Autodesk Fusion 360 part; units mm, degrees
(part 2 of 8)
extrude "Diffuser open rear skirt" add sketch "Diffuser hollow skirt outside profile" against normal blind 2.6 bodies 4
ref_plane "WorkPlane13" through (12.125, -2.4482, 27.9828) normal (0, -0.087156, 0.996195) x (1, 0, 0)
sketch "Diffuser optical cavity profile" plane through (0, -2.4482, 27.9828) normal (0, -0.087156, 0.996195) x (1, 0, 0)
  line L0 (7.7, 94.1972) -> (72.3, 94.1972)
  line L1 (72.3, 94.1972) -> (72.3, 101.7972)
  line L2 (72.3, 101.7972) -> (7.7, 101.7972)
  line L3 (7.7, 101.7972) -> (7.7, 94.1972)
  dimension "d533" = 7.7
  dimension "d534" = 94.1972
  dimension "d535" = 64.6
  dimension "d536" = 7.6
  constraint horizontal L0
  constraint vertical L1
  constraint horizontal L2
  constraint vertical L3
  measures "d533" horizontal distance of origin L0.start
  measures "d534" vertical distance of origin L0.start
  measures "d535" distance of L0.start L0.end
  measures "d536" distance of L0.end L1.end
extrude "Hollow diffuser from inside" cut sketch "Diffuser optical cavity profile" against normal blind 7 bodies 4
sketch "Diffuser right wire exit profile" plane through (0, -2.2216, 25.3927) normal (0, -0.087156, 0.996195) x (1, 0, 0)
  line L0 (71.5, 95.9972) -> (76.5, 95.9972)
  line L1 (76.5, 95.9972) -> (76.5, 99.9972)
  line L2 (76.5, 99.9972) -> (71.5, 99.9972)
  line L3 (71.5, 99.9972) -> (71.5, 95.9972)
  dimension "d539" = 71.5
  dimension "d540" = 95.9972
  dimension "d541" = 5
  dimension "d542" = 4
  constraint horizontal L0
  constraint vertical L1
  constraint horizontal L2
  constraint vertical L3
  measures "d539" horizontal distance of origin L0.start
  measures "d540" vertical distance of origin L0.start
  measures "d541" distance of L0.start L0.end
  measures "d542" distance of L0.end L1.end
extrude "Diffuser right wire exit" cut sketch "Diffuser right wire exit profile" against normal blind 6 bodies 4
sketch "Deep diffuser skirt clearance profile" plane through (0, -2.2739, 25.9904) normal (0, -0.087156, 0.996195) x (1, 0, 0)
  line L0 (5, 91.4972) -> (75, 91.4972)
  line L1 (75, 91.4972) -> (75, 104.4972)
  line L2 (75, 104.4972) -> (5, 104.4972)
  line L3 (5, 104.4972) -> (5, 91.4972)
  dimension "d545" = 5
  dimension "d546" = 91.4972
  dimension "d547" = 70
  dimension "d548" = 13
  constraint horizontal L0
  constraint vertical L1
  constraint horizontal L2
  constraint vertical L3
  measures "d545" horizontal distance of origin L0.start
  measures "d546" vertical distance of origin L0.start
  measures "d547" distance of L0.start L0.end
  measures "d548" distance of L0.end L1.end
extrude "Clear carrier around hollow diffuser" cut sketch "Deep diffuser skirt clearance profile" against normal blind 3.4 bodies 2
sketch "LED rear support web profile" plane through (0, -2.2739, 25.9904) normal (0, -0.087156, 0.996195) x (1, 0, 0)
  line L0 (6.3, 108.1799) -> (73.7, 108.1799)
  line L1 (73.7, 108.1799) -> (73.7, 112.1799)
  line L2 (73.7, 112.1799) -> (6.3, 112.1799)
  line L3 (6.3, 112.1799) -> (6.3, 108.1799)
  dimension "d551" = 6.3
  dimension "d552" = 108.1799
  dimension "d553" = 67.4
  dimension "d554" = 4
  constraint horizontal L0
  constraint vertical L1
  constraint horizontal L2
  constraint vertical L3
  measures "d551" horizontal distance of origin L0.start
  measures "d552" vertical distance of origin L0.start
  measures "d553" distance of L0.start L0.end
  measures "d554" distance of L0.end L1.end
extrude "LED rear support web" add sketch "LED rear support web profile" against normal blind 5.8 bodies 2
ref_plane "WorkPlane14" through (12.125, -1.9775, 22.6033) normal (0, -0.087156, 0.996195) x (1, 0, 0)
sketch "Continuous LED tray profile" plane through (0, -1.9775, 22.6033) normal (0, -0.087156, 0.996195) x (1, 0, 0)
  line L0 (6.3, 92.7972) -> (73.7, 92.7972)
  line L1 (73.7, 92.7972) -> (73.7, 114.4037)
  line L2 (73.7, 114.4037) -> (6.3, 114.4037)
  line L3 (6.3, 114.4037) -> (6.3, 92.7972)
  dimension "d559" = 6.3
  dimension "d560" = 92.7972
  dimension "d561" = 67.4
  dimension "d562" = 21.6065
  constraint horizontal L0
  constraint vertical L1
  constraint horizontal L2
  constraint vertical L3
  measures "d559" horizontal distance of origin L0.start
  measures "d560" vertical distance of origin L0.start
  measures "d561" distance of L0.start L0.end
  measures "d562" distance of L0.end L1.end
extrude "Continuous LED mounting crossbar" add sketch "Continuous LED tray profile" against normal blind 2.4 bodies 2
sketch "LED tray right wire relief profile" plane through (0, -1.9775, 22.6033) normal (0, -0.087156, 0.996195) x (1, 0, 0)
  line L0 (71.5, 95.9972) -> (75.5, 95.9972)
  line L1 (75.5, 95.9972) -> (75.5, 99.9972)
  line L2 (75.5, 99.9972) -> (71.5, 99.9972)
  line L3 (71.5, 99.9972) -> (71.5, 95.9972)
  dimension "d565" = 71.5
  dimension "d566" = 95.9972
  dimension "d567" = 4
  dimension "d568" = 4
  constraint horizontal L0
  constraint vertical L1
  constraint horizontal L2
  constraint vertical L3
  measures "d565" horizontal distance of origin L0.start
  measures "d566" vertical distance of origin L0.start
  measures "d567" distance of L0.start L0.end
  measures "d568" distance of L0.end L1.end
extrude "LED tray right wire relief" cut sketch "LED tray right wire relief profile" against normal blind 3.4 bodies 2
sketch "OLED seat 1 profile" plane through (0, -2.5179, 28.7797) normal (0, -0.087156, 0.996195) x (1, 0, 0)
  line L0 (5.75, 59.4972) -> (41.75, 59.4972)
  line L1 (41.75, 59.4972) -> (41.75, 62.4972)
  line L2 (41.75, 62.4972) -> (5.75, 62.4972)
  line L3 (5.75, 62.4972) -> (5.75, 59.4972)
  dimension "d571" = 5.75
  dimension "d572" = 59.4972
  dimension "d573" = 36
  dimension "d574" = 3
  constraint horizontal L0
  constraint vertical L1
  constraint horizontal L2
  constraint vertical L3
  measures "d571" horizontal distance of origin L0.start
  measures "d572" vertical distance of origin L0.start
  measures "d573" distance of L0.start L0.end
  measures "d574" distance of L0.end L1.end
extrude "OLED opposed locating ledge 1" add sketch "OLED seat 1 profile" against normal blind 2.8 bodies 1
sketch "OLED seat 2 profile" plane through (0, -2.5179, 28.7797) normal (0, -0.087156, 0.996195) x (1, 0, 0)
  line L0 (5.75, 88.4972) -> (41.75, 88.4972)
  line L1 (41.75, 88.4972) -> (41.75, 91.4972)
  line L2 (41.75, 91.4972) -> (5.75, 91.4972)
  line L3 (5.75, 91.4972) -> (5.75, 88.4972)
  dimension "d577" = 5.75
  dimension "d578" = 88.4972
  dimension "d579" = 36
  dimension "d580" = 3
  constraint horizontal L0
  constraint vertical L1
  constraint horizontal L2
  constraint vertical L3
  measures "d577" horizontal distance of origin L0.start
  measures "d578" vertical distance of origin L0.start
  measures "d579" distance of L0.start L0.end
  measures "d580" distance of L0.end L1.end
extrude "OLED opposed locating ledge 2" add sketch "OLED seat 2 profile" against normal blind 2.8 bodies 1
sketch "OLED PCB carrier clearance profile" plane through (0, -2.2739, 25.9904) normal (0, -0.087156, 0.996195) x (1, 0, 0)
  line L0 (5.55, 59.2972) -> (41.95, 59.2972)
  line L1 (41.95, 59.2972) -> (41.95, 93.6972)
  line L2 (41.95, 93.6972) -> (5.55, 93.6972)
  line L3 (5.55, 93.6972) -> (5.55, 59.2972)
  dimension "d583" = 5.55
  dimension "d584" = 59.2972
  dimension "d585" = 36.4
  dimension "d586" = 34.4
  constraint horizontal L0
  constraint vertical L1
  constraint horizontal L2
  constraint vertical L3
  measures "d583" horizontal distance of origin L0.start
  measures "d584" vertical distance of origin L0.start
  measures "d585" distance of L0.start L0.end
  measures "d586" distance of L0.end L1.end
extrude "OLED PCB clearance in carrier" cut sketch "OLED PCB carrier clearance profile" against normal blind 1.8 bodies 2
ref_plane "WorkPlane15" through (12.125, -2.117, 24.1972) normal (0, -0.087156, 0.996195) x (1, 0, 0)
sketch "OLED front clamp root profile" plane through (0, -2.2739, 25.9904) normal (0, -0.087156, 0.996195) x (1, 0, 0)
  line L0 (18, 58.4972) -> (32, 58.4972)
  line L1 (32, 58.4972) -> (32, 59.4972)
  line L2 (32, 59.4972) -> (18, 59.4972)
  line L3 (18, 59.4972) -> (18, 58.4972)
  dimension "d591" = 18
  dimension "d592" = 58.4972
  dimension "d593" = 14
  dimension "d594" = 1
  constraint horizontal L0
  constraint vertical L1
  constraint horizontal L2
  constraint vertical L3
  measures "d591" horizontal distance of origin L0.start
  measures "d592" vertical distance of origin L0.start
  measures "d593" distance of L0.start L0.end
  measures "d594" distance of L0.end L1.end
extrude "OLED front clamp root" add sketch "OLED front clamp root profile" against normal blind 3.8 bodies 2
sketch "OLED front opposed clamp profile" plane through (0, -2.117, 24.1972) normal (0, -0.087156, 0.996195) x (1, 0, 0)
  line L0 (18, 58.4972) -> (32, 58.4972)
  line L1 (32, 58.4972) -> (32, 62.4972)
  line L2 (32, 62.4972) -> (18, 62.4972)
  line L3 (18, 62.4972) -> (18, 58.4972)
  dimension "d597" = 18
  dimension "d598" = 58.4972
  dimension "d599" = 14
  dimension "d600" = 4
  constraint horizontal L0
  constraint vertical L1
  constraint horizontal L2
  constraint vertical L3
  measures "d597" horizontal distance of origin L0.start
  measures "d598" vertical distance of origin L0.start
  measures "d599" distance of L0.start L0.end
  measures "d600" distance of L0.end L1.end
extrude "OLED front opposed clamp" add sketch "OLED front opposed clamp profile" against normal blind 2 bodies 2
sketch "OLED rear clamp connecting bridge profile" plane through (0, -1.9775, 22.6033) normal (0, -0.087156, 0.996195) x (1, 0, 0)
  line L0 (18, 89.2972) -> (32, 89.2972)
  line L1 (32, 89.2972) -> (32, 93.0972)
  line L2 (32, 93.0972) -> (18, 93.0972)
  line L3 (18, 93.0972) -> (18, 89.2972)
  dimension "d603" = 18
  dimension "d604" = 89.2972
  dimension "d605" = 14
  dimension "d606" = 3.8
  constraint horizontal L0
  constraint vertical L1
  constraint horizontal L2
  constraint vertical L3
  measures "d603" horizontal distance of origin L0.start
  measures "d604" vertical distance of origin L0.start
  measures "d605" distance of L0.start L0.end
  measures "d606" distance of L0.end L1.end
extrude "OLED rear clamp connecting bridge" add sketch "OLED rear clamp connecting bridge profile" against normal blind 2.4 bodies 2
sketch "OLED rear opposed clamp profile" plane through (0, -2.117, 24.1972) normal (0, -0.087156, 0.996195) x (1, 0, 0)
  line L0 (18, 89.4972) -> (32, 89.4972)
  line L1 (32, 89.4972) -> (32, 91.4972)
  line L2 (32, 91.4972) -> (18, 91.4972)
  line L3 (18, 91.4972) -> (18, 89.4972)
  dimension "d609" = 18
  dimension "d610" = 89.4972
  dimension "d611" = 14
  dimension "d612" = 2
  constraint horizontal L0
  constraint vertical L1
  constraint horizontal L2
  constraint vertical L3
  measures "d609" horizontal distance of origin L0.start
  measures "d610" vertical distance of origin L0.start
  measures "d611" distance of L0.start L0.end
  measures "d612" distance of L0.end L1.end
extrude "OLED rear opposed clamp" add sketch "OLED rear opposed clamp profile" against normal blind 2 bodies 2
sketch "OLED PCB carrier clearance profile (1)" plane through (0, -2.2739, 25.9904) normal (0, -0.087156, 0.996195) x (1, 0, 0)
  line L0 (5.55, 59.2972) -> (41.95, 59.2972)
  line L1 (41.95, 59.2972) -> (41.95, 93.6972)
  line L2 (41.95, 93.6972) -> (5.55, 93.6972)
  line L3 (5.55, 93.6972) -> (5.55, 59.2972)
  dimension "d615" = 5.55
  dimension "d616" = 59.2972
  dimension "d617" = 36.4
  dimension "d618" = 34.4
  constraint horizontal L0
  constraint vertical L1
  constraint horizontal L2
  constraint vertical L3
  measures "d615" horizontal distance of origin L0.start
  measures "d616" vertical distance of origin L0.start
  measures "d617" distance of L0.start L0.end
  measures "d618" distance of L0.end L1.end
extrude "OLED PCB clearance in carrier (1)" cut sketch "OLED PCB carrier clearance profile (1)" against normal blind 1.8 bodies 2
ref_plane "WorkPlane16" through (0, 0, 26.3) normal (0, 0, 1) x (1, 0, 0)
sketch "PCB1 perimeter support profile" plane through (0, 0, 26.3) normal (0, 0, 1) x (1, 0, 0)
  line L0 (3.2, 62.2) -> (4.8, 62.2)
  line L1 (4.8, 62.2) -> (4.8, 66.2)
  line L2 (4.8, 66.2) -> (3.2, 66.2)
  line L3 (3.2, 66.2) -> (3.2, 62.2)
  dimension "d623" = 3.2
  dimension "d624" = 62.2
  dimension "d625" = 1.6
  dimension "d626" = 4
  constraint horizontal L0
  constraint vertical L1
  constraint horizontal L2
  constraint vertical L3
  measures "d623" horizontal distance of origin L0.start
  measures "d624" vertical distance of origin L0.start
  measures "d625" distance of L0.start L0.end
  measures "d626" distance of L0.end L1.end
sketch "PCB1 short post bridge profile" plane through (0, 0, 26.3) normal (0, 0, 1) x (1, 0, 0)
  line L0 (3.2, 62.2) -> (7, 62.2)
  line L1 (7, 62.2) -> (7, 66.2)
  line L2 (7, 66.2) -> (3.2, 66.2)
  line L3 (3.2, 66.2) -> (3.2, 62.2)
  dimension "d629" = 3.2
  dimension "d630" = 62.2
  dimension "d631" = 3.8
  dimension "d632" = 4
  constraint horizontal L0
  constraint vertical L1
  constraint horizontal L2
  constraint vertical L3
  measures "d629" horizontal distance of origin L0.start
  measures "d630" vertical distance of origin L0.start
  measures "d631" distance of L0.start L0.end
  measures "d632" distance of L0.end L1.end
sketch "PCB1 post profile" plane through (0, 0, 22.3) normal (0, 0, 1) x (1, 0, 0)
  circle A0 centre (7, 64.2) radius 2.2
  dimension "d635" = 7
  dimension "d636" = 64.2
  dimension "d637" = 4.4
  measures "d635" horizontal distance of origin A0.centre
  measures "d636" vertical distance of origin A0.centre
  measures "d637" diameter of A0
sketch "PCB1 M2 pilot profile" plane through (0, 0, 22.3) normal (0, 0, 1) x (1, 0, 0)
  circle A0 centre (7, 64.2) radius 0.85
  dimension "d640" = 7
  dimension "d641" = 64.2
  dimension "d642" = 1.7
  measures "d640" horizontal distance of origin A0.centre
  measures "d641" vertical distance of origin A0.centre
  measures "d642" diameter of A0
sketch "PCB2 perimeter support profile" plane through (0, 0, 26.3) normal (0, 0, 1) x (1, 0, 0)
  line L0 (75.2, 62.2) -> (76.8, 62.2)
  line L1 (76.8, 62.2) -> (76.8, 66.2)
  line L2 (76.8, 66.2) -> (75.2, 66.2)
  line L3 (75.2, 66.2) -> (75.2, 62.2)
  dimension "d645" = 75.2
  dimension "d646" = 62.2
  dimension "d647" = 1.6
  dimension "d648" = 4
  constraint horizontal L0
  constraint vertical L1
  constraint horizontal L2
  constraint vertical L3
  measures "d645" horizontal distance of origin L0.start
  measures "d646" vertical distance of origin L0.start
  measures "d647" distance of L0.start L0.end
  measures "d648" distance of L0.end L1.end
sketch "PCB2 short post bridge profile" plane through (0, 0, 26.3) normal (0, 0, 1) x (1, 0, 0)
  line L0 (73, 62.2) -> (76.8, 62.2)
  line L1 (76.8, 62.2) -> (76.8, 66.2)
  line L2 (76.8, 66.2) -> (73, 66.2)
  line L3 (73, 66.2) -> (73, 62.2)
  dimension "d651" = 73
  dimension "d652" = 62.2
  dimension "d653" = 3.8
  dimension "d654" = 4
  constraint horizontal L0
  constraint vertical L1
  constraint horizontal L2
  constraint vertical L3
  measures "d651" horizontal distance of origin L0.start
  measures "d652" vertical distance of origin L0.start
  measures "d653" distance of L0.start L0.end
  measures "d654" distance of L0.end L1.end
sketch "PCB2 post profile" plane through (0, 0, 22.3) normal (0, 0, 1) x (1, 0, 0)
  circle A0 centre (73, 64.2) radius 2.2
  dimension "d657" = 73
  dimension "d658" = 64.2
  dimension "d659" = 4.4
  measures "d657" horizontal distance of origin A0.centre
  measures "d658" vertical distance of origin A0.centre
  measures "d659" diameter of A0
sketch "PCB2 M2 pilot profile" plane through (0, 0, 22.3) normal (0, 0, 1) x (1, 0, 0)
  circle A0 centre (73, 64.2) radius 0.85
  dimension "d662" = 73
  dimension "d663" = 64.2
  dimension "d664" = 1.7
  measures "d662" horizontal distance of origin A0.centre
  measures "d663" vertical distance of origin A0.centre
  measures "d664" diameter of A0
sketch "PCB3 perimeter support profile" plane through (0, 0, 26.3) normal (0, 0, 1) x (1, 0, 0)
  line L0 (3.2, 108.2) -> (4.8, 108.2)
  line L1 (4.8, 108.2) -> (4.8, 112.2)
  line L2 (4.8, 112.2) -> (3.2, 112.2)
  line L3 (3.2, 112.2) -> (3.2, 108.2)
  dimension "d667" = 3.2
  dimension "d668" = 108.2
  dimension "d669" = 1.6
  dimension "d670" = 4
  constraint horizontal L0
  constraint vertical L1
  constraint horizontal L2
  constraint vertical L3
  measures "d667" horizontal distance of origin L0.start
  measures "d668" vertical distance of origin L0.start
  measures "d669" distance of L0.start L0.end
  measures "d670" distance of L0.end L1.end
sketch "PCB3 short post bridge profile" plane through (0, 0, 26.3) normal (0, 0, 1) x (1, 0, 0)
  line L0 (3.2, 108.2) -> (7, 108.2)
  line L1 (7, 108.2) -> (7, 112.2)
  line L2 (7, 112.2) -> (3.2, 112.2)
  line L3 (3.2, 112.2) -> (3.2, 108.2)
  dimension "d673" = 3.2
  dimension "d674" = 108.2
  dimension "d675" = 3.8
  dimension "d676" = 4
  constraint horizontal L0
  constraint vertical L1
  constraint horizontal L2
  constraint vertical L3
  measures "d673" horizontal distance of origin L0.start
  measures "d674" vertical distance of origin L0.start
  measures "d675" distance of L0.start L0.end
  measures "d676" distance of L0.end L1.end
sketch "PCB3 post profile" plane through (0, 0, 22.3) normal (0, 0, 1) x (1, 0, 0)
  circle A0 centre (7, 110.2) radius 2.2
  dimension "d679" = 7
  dimension "d680" = 110.2
  dimension "d681" = 4.4
  measures "d679" horizontal distance of origin A0.centre
  measures "d680" vertical distance of origin A0.centre
  measures "d681" diameter of A0
sketch "PCB3 M2 pilot profile" plane through (0, 0, 22.3) normal (0, 0, 1) x (1, 0, 0)
  circle A0 centre (7, 110.2) radius 0.85
  dimension "d684" = 7
  dimension "d685" = 110.2
  dimension "d686" = 1.7
  measures "d684" horizontal distance of origin A0.centre
  measures "d685" vertical distance of origin A0.centre
  measures "d686" diameter of A0
sketch "PCB4 perimeter support profile" plane through (0, 0, 26.3) normal (0, 0, 1) x (1, 0, 0)
  line L0 (75.2, 108.2) -> (76.8, 108.2)
  line L1 (76.8, 108.2) -> (76.8, 112.2)
  line L2 (76.8, 112.2) -> (75.2, 112.2)
  line L3 (75.2, 112.2) -> (75.2, 108.2)
  dimension "d689" = 75.2
  dimension "d690" = 108.2
  dimension "d691" = 1.6
  dimension "d692" = 4
  constraint horizontal L0
  constraint vertical L1
  constraint horizontal L2
  constraint vertical L3
  measures "d689" horizontal distance of origin L0.start
  measures "d690" vertical distance of origin L0.start
  measures "d691" distance of L0.start L0.end
  measures "d692" distance of L0.end L1.end
sketch "PCB4 short post bridge profile" plane through (0, 0, 26.3) normal (0, 0, 1) x (1, 0, 0)
  line L0 (73, 108.2) -> (76.8, 108.2)
  line L1 (76.8, 108.2) -> (76.8, 112.2)
  line L2 (76.8, 112.2) -> (73, 112.2)
  line L3 (73, 112.2) -> (73, 108.2)
  dimension "d695" = 73
  dimension "d696" = 108.2
  dimension "d697" = 3.8
  dimension "d698" = 4
  constraint horizontal L0
  constraint vertical L1
  constraint horizontal L2
  constraint vertical L3
  measures "d695" horizontal distance of origin L0.start
  measures "d696" vertical distance of origin L0.start
  measures "d697" distance of L0.start L0.end
  measures "d698" distance of L0.end L1.end
sketch "PCB4 post profile" plane through (0, 0, 22.3) normal (0, 0, 1) x (1, 0, 0)
  circle A0 centre (73, 110.2) radius 2.2
  dimension "d701" = 73
  dimension "d702" = 110.2
  dimension "d703" = 4.4
  measures "d701" horizontal distance of origin A0.centre
  measures "d702" vertical distance of origin A0.centre
  measures "d703" diameter of A0
sketch "PCB4 M2 pilot profile" plane through (0, 0, 22.3) normal (0, 0, 1) x (1, 0, 0)
  circle A0 centre (73, 110.2) radius 0.85
  dimension "d706" = 73
  dimension "d707" = 110.2
  dimension "d708" = 1.7
  measures "d706" horizontal distance of origin A0.centre
  measures "d707" vertical distance of origin A0.centre
  measures "d708" diameter of A0
ref_plane "WorkPlane17" through (12.125, -1.8381, 21.0094) normal (0, -0.087156, 0.996195) x (1, 0, 0)
sketch "M1 carrier stop profile" plane through (0, -1.8729, 21.4079) normal (0, -0.087156, 0.996195) x (1, 0, 0)
  circle A0 centre (12, 13.0275) radius 3.5
  dimension "d713" = 12
  dimension "d715" = 7
  measures "d713" horizontal distance of origin A0.centre
  measures "d715" diameter of A0
extrude "M1 rigid carrier stop" add sketch "M1 carrier stop profile" against normal blind 0.4 bodies 1
sketch "M1 stop insert entry profile" plane through (0, -1.8381, 21.0094) normal (0, -0.087156, 0.996195) x (1, 0, 0)
  circle A0 centre (12, 13.0275) radius 1.6
  dimension "d718" = 12
  dimension "d720" = 3.2
  measures "d718" horizontal distance of origin A0.centre
  measures "d720" diameter of A0
extrude "M1 open stop insert entry" cut sketch "M1 stop insert entry profile" along normal blind 0.5 bodies 1
sketch "M2 carrier stop profile" plane through (0, -1.8729, 21.4079) normal (0, -0.087156, 0.996195) x (1, 0, 0)
  circle A0 centre (68, 13.0275) radius 3.5
  dimension "d723" = 68
  dimension "d725" = 7
  measures "d723" horizontal distance of origin A0.centre
  measures "d725" diameter of A0
extrude "M2 rigid carrier stop" add sketch "M2 carrier stop profile" against normal blind 0.4 bodies 1
sketch "M2 stop insert entry profile" plane through (0, -1.8381, 21.0094) normal (0, -0.087156, 0.996195) x (1, 0, 0)
  circle A0 centre (68, 13.0275) radius 1.6
  dimension "d728" = 68
  dimension "d730" = 3.2
  measures "d728" horizontal distance of origin A0.centre
  measures "d730" diameter of A0
extrude "M2 open stop insert entry" cut sketch "M2 stop insert entry profile" along normal blind 0.5 bodies 1
sketch "M3 carrier stop profile" plane through (0, -1.8729, 21.4079) normal (0, -0.087156, 0.996195) x (1, 0, 0)
  circle A0 centre (12, 108.3268) radius 3.5
  dimension "d733" = 12
  dimension "d735" = 7
  measures "d733" horizontal distance of origin A0.centre
  measures "d735" diameter of A0
extrude "M3 rigid carrier stop" add sketch "M3 carrier stop profile" against normal blind 0.4 bodies 1
sketch "M3 stop insert entry profile" plane through (0, -1.8381, 21.0094) normal (0, -0.087156, 0.996195) x (1, 0, 0)
  circle A0 centre (12, 108.3268) radius 1.6
  dimension "d738" = 12
  dimension "d740" = 3.2
  measures "d738" horizontal distance of origin A0.centre
  measures "d740" diameter of A0
extrude "M3 open stop insert entry" cut sketch "M3 stop insert entry profile" along normal blind 0.5 bodies 1
sketch "M3 restored carrier pocket profile" plane through (0, -1.8381, 21.0094) normal (0, -0.087156, 0.996195) x (1, 0, 0)
  circle A0 centre (12, 108.3268) radius 4.2024
  dimension "d743" = 12
  dimension "d745" = 8.4049
  measures "d743" horizontal distance of origin A0.centre
  measures "d745" diameter of A0
extrude "M3 restored carrier pocket" cut sketch "M3 restored carrier pocket profile" along normal blind 7.8 bodies 2
sketch "M3 restored screw clearance profile" plane through (0, -2.2739, 25.9904) normal (0, -0.087156, 0.996195) x (1, 0, 0)
  circle A0 centre (12, 108.3268) radius 1.15
  dimension "d748" = 12
  dimension "d750" = 2.3
  measures "d748" horizontal distance of origin A0.centre
  measures "d750" diameter of A0
extrude "M3 restored screw clearance" cut sketch "M3 restored screw clearance profile" against normal blind 10 bodies 2
sketch "M3 restored cover boss relief profile" plane through (0, 0, 2) normal (0, 0, 1) x (1, 0, 0)
  circle A0 centre (20, 112) radius 3.2
  dimension "d753" = 20
  dimension "d754" = 112
  dimension "d755" = 6.4
  measures "d753" horizontal distance of origin A0.centre
  measures "d754" vertical distance of origin A0.centre
  measures "d755" diameter of A0
extrude "M3 restored cover boss relief" cut sketch "M3 restored cover boss relief profile" along normal blind 40.0612 bodies 2
sketch "M4 carrier stop profile" plane through (0, -1.8729, 21.4079) normal (0, -0.087156, 0.996195) x (1, 0, 0)
  circle A0 centre (68, 108.3268) radius 3.5
  dimension "d758" = 68
  dimension "d760" = 7
  measures "d758" horizontal distance of origin A0.centre
  measures "d760" diameter of A0
extrude "M4 rigid carrier stop" add sketch "M4 carrier stop profile" against normal blind 0.4 bodies 1
sketch "M4 stop insert entry profile" plane through (0, -1.8381, 21.0094) normal (0, -0.087156, 0.996195) x (1, 0, 0)
  circle A0 centre (68, 108.3268) radius 1.6
  dimension "d763" = 68
  dimension "d765" = 3.2
  measures "d763" horizontal distance of origin A0.centre
  measures "d765" diameter of A0
extrude "M4 open stop insert entry" cut sketch "M4 stop insert entry profile" along normal blind 0.5 bodies 1
sketch "M4 restored carrier pocket profile" plane through (0, -1.8381, 21.0094) normal (0, -0.087156, 0.996195) x (1, 0, 0)
  circle A0 centre (68, 108.3268) radius 4.2024
  dimension "d768" = 68
  dimension "d770" = 8.4049
  measures "d768" horizontal distance of origin A0.centre
  measures "d770" diameter of A0
extrude "M4 restored carrier pocket" cut sketch "M4 restored carrier pocket profile" along normal blind 7.8 bodies 2
sketch "M4 restored screw clearance profile" plane through (0, -2.2739, 25.9904) normal (0, -0.087156, 0.996195) x (1, 0, 0)
  circle A0 centre (68, 108.3268) radius 1.15
  dimension "d773" = 68
  dimension "d775" = 2.3
  measures "d773" horizontal distance of origin A0.centre
  measures "d775" diameter of A0
extrude "M4 restored screw clearance" cut sketch "M4 restored screw clearance profile" against normal blind 10 bodies 2
sketch "M4 restored cover boss relief profile" plane through (0, 0, 2) normal (0, 0, 1) x (1, 0, 0)
  circle A0 centre (60, 112) radius 3.2
  dimension "d778" = 60
  dimension "d779" = 112
  dimension "d780" = 6.4
  measures "d778" horizontal distance of origin A0.centre
  measures "d779" vertical distance of origin A0.centre
  measures "d780" diameter of A0
extrude "M4 restored cover boss relief" cut sketch "M4 restored cover boss relief profile" along normal blind 40.0612 bodies 2
ref_plane "WorkPlane18" through (3.2, 0, 0) normal (1, 0, 0) x (0, 1, 0)
sketch "PCB direct rail 1 profile" plane through (3.2, 0, 0) normal (1, 0, 0) x (0, 0, -1)
  line L0 (-27.8, 62.2) -> (-27.8, 112.2)
  line L1 (-27.8, 112.2) -> (-34.8009, 112.2)
  line L2 (-34.8009, 112.2) -> (-30.4265, 62.2)
  line L3 (-30.4265, 62.2) -> (-27.8, 62.2)
  dimension "d788" = 27.8
  dimension "d789" = 62.2
  dimension "d790" = 50
  dimension "d791" = 7.0009
  dimension "d792" = 2.6265
  constraint vertical L0
  constraint horizontal L1
  constraint horizontal L3
  measures "d788" horizontal distance of origin L0.start
  measures "d789" vertical distance of origin L0.start
  measures "d790" distance of L0.start L0.end
  measures "d791" distance of L0.end L1.end
  measures "d792" distance of L0.start L2.end
extrude "PCB direct rail 1" add sketch "PCB direct rail 1 profile" along normal blind 1.6 bodies 2
ref_plane "WorkPlane19" through (75.2, 0, 0) normal (1, 0, 0) x (0, 1, 0)
sketch "PCB direct rail 2 profile" plane through (75.2, 0, 0) normal (1, 0, 0) x (0, 0, -1)
  line L0 (-27.8, 62.2) -> (-27.8, 112.2)
  line L1 (-27.8, 112.2) -> (-34.8009, 112.2)
  line L2 (-34.8009, 112.2) -> (-30.4265, 62.2)
  line L3 (-30.4265, 62.2) -> (-27.8, 62.2)
  dimension "d797" = 27.8
  dimension "d798" = 62.2
  dimension "d799" = 50
  dimension "d800" = 7.0009
  dimension "d801" = 2.6265
  constraint vertical L0
  constraint horizontal L1
  constraint horizontal L3
  measures "d797" horizontal distance of origin L0.start
  measures "d798" vertical distance of origin L0.start
  measures "d799" distance of L0.start L0.end
  measures "d800" distance of L0.end L1.end
  measures "d801" distance of L0.start L2.end
extrude "PCB direct rail 2" add sketch "PCB direct rail 2 profile" along normal blind 1.6 bodies 2
ref_plane "WorkPlane20" through (0, 0, 27.8) normal (0, 0, 1) x (1, 0, 0)
sketch "PCB direct mount 1 ear profile" plane through (0, 0, 27.8) normal (0, 0, 1) x (1, 0, 0)
  line L0 (3.2, 62) -> (9.2, 62)
  line L1 (9.2, 62) -> (9.2, 66.4)
  line L2 (9.2, 66.4) -> (3.2, 66.4)
  line L3 (3.2, 66.4) -> (3.2, 62)
  dimension "d806" = 3.2
  dimension "d807" = 62
  dimension "d808" = 6
  dimension "d809" = 4.4
  constraint horizontal L0
  constraint vertical L1
  constraint horizontal L2
  constraint vertical L3
  measures "d806" horizontal distance of origin L0.start
  measures "d807" vertical distance of origin L0.start
  measures "d808" distance of L0.start L0.end
  measures "d809" distance of L0.end L1.end
extrude "PCB direct mount 1 ear" add sketch "PCB direct mount 1 ear profile" along normal blind 1.5 bodies 2
sketch "PCB direct mount 1 boss profile" plane through (0, 0, 22.3) normal (0, 0, 1) x (1, 0, 0)
  circle A0 centre (7, 64.2) radius 2.2
  dimension "d812" = 7
  dimension "d813" = 64.2
  dimension "d814" = 4.4
  measures "d812" horizontal distance of origin A0.centre
  measures "d813" vertical distance of origin A0.centre
  measures "d814" diameter of A0
extrude "PCB direct mount 1 boss" add sketch "PCB direct mount 1 boss profile" along normal blind 7 bodies 2
sketch "PCB direct mount 1 screw profile" plane through (0, 0, 22.3) normal (0, 0, 1) x (1, 0, 0)
  circle A0 centre (7, 64.2) radius 0.85
  dimension "d817" = 7
  dimension "d818" = 64.2
  dimension "d819" = 1.7
  measures "d817" horizontal distance of origin A0.centre
  measures "d818" vertical distance of origin A0.centre
  measures "d819" diameter of A0
extrude "PCB direct mount 1 screw pilot" cut sketch "PCB direct mount 1 screw profile" along normal blind 4.5 bodies 2
sketch "PCB direct mount 2 ear profile" plane through (0, 0, 27.8) normal (0, 0, 1) x (1, 0, 0)
  line L0 (70.8, 62) -> (76.8, 62)
  line L1 (76.8, 62) -> (76.8, 66.4)
  line L2 (76.8, 66.4) -> (70.8, 66.4)
  line L3 (70.8, 66.4) -> (70.8, 62)
  dimension "d822" = 70.8
  dimension "d823" = 62
  dimension "d824" = 6
  dimension "d825" = 4.4
  constraint horizontal L0
  constraint vertical L1
  constraint horizontal L2
  constraint vertical L3
  measures "d822" horizontal distance of origin L0.start
  measures "d823" vertical distance of origin L0.start
  measures "d824" distance of L0.start L0.end
  measures "d825" distance of L0.end L1.end
extrude "PCB direct mount 2 ear" add sketch "PCB direct mount 2 ear profile" along normal blind 1.5 bodies 2
sketch "PCB direct mount 2 boss profile" plane through (0, 0, 22.3) normal (0, 0, 1) x (1, 0, 0)
  circle A0 centre (73, 64.2) radius 2.2
  dimension "d828" = 73
  dimension "d829" = 64.2
  dimension "d830" = 4.4
  measures "d828" horizontal distance of origin A0.centre
  measures "d829" vertical distance of origin A0.centre
  measures "d830" diameter of A0
extrude "PCB direct mount 2 boss" add sketch "PCB direct mount 2 boss profile" along normal blind 7 bodies 2
sketch "PCB direct mount 2 screw profile" plane through (0, 0, 22.3) normal (0, 0, 1) x (1, 0, 0)
  circle A0 centre (73, 64.2) radius 0.85
  dimension "d833" = 73
  dimension "d834" = 64.2
  dimension "d835" = 1.7
  measures "d833" horizontal distance of origin A0.centre
  measures "d834" vertical distance of origin A0.centre
  measures "d835" diameter of A0
extrude "PCB direct mount 2 screw pilot" cut sketch "PCB direct mount 2 screw profile" along normal blind 4.5 bodies 2
sketch "PCB direct mount 3 ear profile" plane through (0, 0, 27.8) normal (0, 0, 1) x (1, 0, 0)
  line L0 (3.2, 108) -> (9.2, 108)
  line L1 (9.2, 108) -> (9.2, 112.4)
  line L2 (9.2, 112.4) -> (3.2, 112.4)
  line L3 (3.2, 112.4) -> (3.2, 108)
  dimension "d838" = 3.2
  dimension "d839" = 108
  dimension "d840" = 6
  dimension "d841" = 4.4
  constraint horizontal L0
  constraint vertical L1
  constraint horizontal L2
  constraint vertical L3
  measures "d838" horizontal distance of origin L0.start
  measures "d839" vertical distance of origin L0.start
  measures "d840" distance of L0.start L0.end
  measures "d841" distance of L0.end L1.end
extrude "PCB direct mount 3 ear" add sketch "PCB direct mount 3 ear profile" along normal blind 1.5 bodies 2
sketch "PCB direct mount 3 boss profile" plane through (0, 0, 22.3) normal (0, 0, 1) x (1, 0, 0)
  circle A0 centre (7, 110.2) radius 2.2
  dimension "d844" = 7
  dimension "d845" = 110.2
  dimension "d846" = 4.4
  measures "d844" horizontal distance of origin A0.centre
  measures "d845" vertical distance of origin A0.centre
  measures "d846" diameter of A0
extrude "PCB direct mount 3 boss" add sketch "PCB direct mount 3 boss profile" along normal blind 7 bodies 2
sketch "PCB direct mount 3 screw profile" plane through (0, 0, 22.3) normal (0, 0, 1) x (1, 0, 0)
  circle A0 centre (7, 110.2) radius 0.85
  dimension "d849" = 7
  dimension "d850" = 110.2
  dimension "d851" = 1.7
  measures "d849" horizontal distance of origin A0.centre
  measures "d850" vertical distance of origin A0.centre
  measures "d851" diameter of A0
extrude "PCB direct mount 3 screw pilot" cut sketch "PCB direct mount 3 screw profile" along normal blind 4.5 bodies 2
sketch "PCB direct mount 4 ear profile" plane through (0, 0, 27.8) normal (0, 0, 1) x (1, 0, 0)
  line L0 (70.8, 108) -> (76.8, 108)
  line L1 (76.8, 108) -> (76.8, 112.4)
  line L2 (76.8, 112.4) -> (70.8, 112.4)
  line L3 (70.8, 112.4) -> (70.8, 108)
  dimension "d854" = 70.8
  dimension "d855" = 108
  dimension "d856" = 6
  dimension "d857" = 4.4
  constraint horizontal L0
  constraint vertical L1
  constraint horizontal L2
  constraint vertical L3
  measures "d854" horizontal distance of origin L0.start
  measures "d855" vertical distance of origin L0.start
  measures "d856" distance of L0.start L0.end
  measures "d857" distance of L0.end L1.end
extrude "PCB direct mount 4 ear" add sketch "PCB direct mount 4 ear profile" along normal blind 1.5 bodies 2
sketch "PCB direct mount 4 boss profile" plane through (0, 0, 22.3) normal (0, 0, 1) x (1, 0, 0)
  circle A0 centre (73, 110.2) radius 2.2
  dimension "d860" = 73
  dimension "d861" = 110.2
  dimension "d862" = 4.4
  measures "d860" horizontal distance of origin A0.centre
  measures "d861" vertical distance of origin A0.centre
  measures "d862" diameter of A0
extrude "PCB direct mount 4 boss" add sketch "PCB direct mount 4 boss profile" along normal blind 7 bodies 2
sketch "PCB direct mount 4 screw profile" plane through (0, 0, 22.3) normal (0, 0, 1) x (1, 0, 0)
  circle A0 centre (73, 110.2) radius 0.85
  dimension "d865" = 73
  dimension "d866" = 110.2
  dimension "d867" = 1.7
  measures "d865" horizontal distance of origin A0.centre
  measures "d866" vertical distance of origin A0.centre
  measures "d867" diameter of A0
extrude "PCB direct mount 4 screw pilot" cut sketch "PCB direct mount 4 screw profile" along normal blind 4.5 bodies 2
ref_plane "WorkPlane21" through (12.125, -2.1431, 24.4961) normal (0, -0.087156, 0.996195) x (1, 0, 0)
ref_plane "WorkPlane22" through (12.125, -1.6638, 19.017) normal (0, -0.087156, 0.996195) x (1, 0, 0)
ref_plane "WorkPlane23" through (12.125, -1.2106, 13.8368) normal (0, -0.087156, 0.996195) x (1, 0, 0)
ref_plane "WorkPlane24" through (12.125, -2.056, 23.4999) normal (0, -0.087156, 0.996195) x (1, 0, 0)
ref_plane "WorkPlane25" through (12.125, -1.1931, 13.6376) normal (0, -0.087156, 0.996195) x (1, 0, 0)
ref_plane "WorkPlane26" through (0, 0, 2) normal (0, 0, 1) x (1, 0, 0)
sketch "SW1 receiver profile" plane through (0, -2.1431, 24.4961) normal (0, -0.087156, 0.996195) x (1, 0, 0)
  line L0 (6.3, 17.6972) -> (24.7, 17.6972)
  line L1 (24.7, 17.6972) -> (24.7, 35.2972)
  line L2 (24.7, 35.2972) -> (6.3, 35.2972)
  line L3 (6.3, 35.2972) -> (6.3, 17.6972)
  dimension "d896" = 6.3
  dimension "d897" = 17.6972
  dimension "d898" = 18.4
  dimension "d899" = 17.6
  constraint horizontal L0
  constraint vertical L1
  constraint horizontal L2
  constraint vertical L3
  measures "d896" horizontal distance of origin L0.start
  measures "d897" vertical distance of origin L0.start
  measures "d898" distance of L0.start L0.end
  measures "d899" distance of L0.end L1.end
extrude "SW1 integrated receiver" add sketch "SW1 receiver profile" against normal blind 11.5 bodies 2
sketch "SW1 switch lower clearance profile" plane through (0, -2.1431, 24.4961) normal (0, -0.087156, 0.996195) x (1, 0, 0)
  line L0 (7.5, 18.4972) -> (23.5, 18.4972)
  line L1 (23.5, 18.4972) -> (23.5, 34.4972)
  line L2 (23.5, 34.4972) -> (7.5, 34.4972)
  line L3 (7.5, 34.4972) -> (7.5, 18.4972)
  dimension "d902" = 7.5
  dimension "d903" = 18.4972
  dimension "d904" = 16
  dimension "d905" = 16
  constraint horizontal L0
  constraint vertical L1
  constraint horizontal L2
  constraint vertical L3
  measures "d902" horizontal distance of origin L0.start
  measures "d903" vertical distance of origin L0.start
  measures "d904" distance of L0.start L0.end
  measures "d905" distance of L0.end L1.end
extrude "SW1 switch lower clearance" cut sketch "SW1 switch lower clearance profile" against normal blind 5.5 bodies 2
sketch "SW1 holder pocket profile" plane through (0, -1.6638, 19.017) normal (0, -0.087156, 0.996195) x (1, 0, 0)
  line L0 (9.7843, 21.4226) -> (21.2157, 21.4226)
  line L1 (21.2157, 21.4226) -> (21.2157, 31.5717)
  line L2 (21.2157, 31.5717) -> (9.7843, 31.5717)
  line L3 (9.7843, 31.5717) -> (9.7843, 21.4226)
  dimension "d908" = 9.7843
  dimension "d909" = 21.4226
  dimension "d910" = 11.4315
  dimension "d911" = 10.1491
  constraint horizontal L0
  constraint vertical L1
  constraint horizontal L2
  constraint vertical L3
  measures "d908" horizontal distance of origin L0.start
  measures "d909" vertical distance of origin L0.start
  measures "d910" distance of L0.start L0.end
  measures "d911" distance of L0.end L1.end
extrude "SW1 open-bottom holder pocket" cut sketch "SW1 holder pocket profile" against normal blind 6.2 bodies 2
sketch "SW1 spring 1 release 1 profile" plane through (0, -2.056, 23.4999) normal (0, -0.087156, 0.996195) x (1, 0, 0)
  line L0 (6.2, 28.5972) -> (9.7843, 28.5972)
  line L1 (9.7843, 28.5972) -> (9.7843, 29.1972)
  line L2 (9.7843, 29.1972) -> (6.2, 29.1972)
  line L3 (6.2, 29.1972) -> (6.2, 28.5972)
  dimension "d914" = 6.2
  dimension "d915" = 28.5972
  dimension "d916" = 3.5843
  dimension "d917" = 0.6
  constraint horizontal L0
  constraint vertical L1
  constraint horizontal L2
  constraint vertical L3
  measures "d914" horizontal distance of origin L0.start
  measures "d915" vertical distance of origin L0.start
  measures "d916" distance of L0.start L0.end
  measures "d917" distance of L0.end L1.end
extrude "SW1 spring 1 release 1" cut sketch "SW1 spring 1 release 1 profile" against normal blind 10.7 bodies 2
sketch "SW1 spring 1 release 2 profile" plane through (0, -2.056, 23.4999) normal (0, -0.087156, 0.996195) x (1, 0, 0)
  line L0 (6.2, 31.1972) -> (9.7843, 31.1972)
  line L1 (9.7843, 31.1972) -> (9.7843, 31.7972)
  line L2 (9.7843, 31.7972) -> (6.2, 31.7972)
  line L3 (6.2, 31.7972) -> (6.2, 31.1972)
  dimension "d920" = 6.2
  dimension "d921" = 31.1972
  dimension "d922" = 3.5843
  dimension "d923" = 0.6
  constraint horizontal L0
  constraint vertical L1
  constraint horizontal L2
  constraint vertical L3
  measures "d920" horizontal distance of origin L0.start
  measures "d921" vertical distance of origin L0.start
  measures "d922" distance of L0.start L0.end
  measures "d923" distance of L0.end L1.end
extrude "SW1 spring 1 release 2" cut sketch "SW1 spring 1 release 2 profile" against normal blind 10.7 bodies 2
sketch "SW1 spring 1 inner clearance profile" plane through (0, -1.6638, 19.017) normal (0, -0.087156, 0.996195) x (1, 0, 0)
  line L0 (7.1, 29.1972) -> (9.7843, 29.1972)
  line L1 (9.7843, 29.1972) -> (9.7843, 31.1972)
  line L2 (9.7843, 31.1972) -> (7.1, 31.1972)
  line L3 (7.1, 31.1972) -> (7.1, 29.1972)
  dimension "d926" = 7.1
  dimension "d927" = 29.1972
  dimension "d928" = 2.6843
  dimension "d929" = 2
  constraint horizontal L0
  constraint vertical L1
  constraint horizontal L2
  constraint vertical L3
  measures "d926" horizontal distance of origin L0.start
  measures "d927" vertical distance of origin L0.start
  measures "d928" distance of L0.start L0.end
  measures "d929" distance of L0.end L1.end
extrude "SW1 spring 1 inner clearance" cut sketch "SW1 spring 1 inner clearance profile" against normal blind 6.2 bodies 2
sketch "SW1 spring 1 hook profile" plane through (0, -1.2106, 13.8368) normal (0, -0.087156, 0.996195) x (1, 0, 0)
  line L0 (6.3, 29.1972) -> (10.2843, 29.1972)
  line L1 (10.2843, 29.1972) -> (10.2843, 31.1972)
  line L2 (10.2843, 31.1972) -> (6.3, 31.1972)
  line L3 (6.3, 31.1972) -> (6.3, 29.1972)
  dimension "d932" = 6.3
  dimension "d933" = 29.1972
  dimension "d934" = 3.9843
  dimension "d935" = 2
  constraint horizontal L0
  constraint vertical L1
  constraint horizontal L2
  constraint vertical L3
  measures "d932" horizontal distance of origin L0.start
  measures "d933" vertical distance of origin L0.start
  measures "d934" distance of L0.start L0.end
  measures "d935" distance of L0.end L1.end
extrude "SW1 spring 1 retaining hook" add sketch "SW1 spring 1 hook profile" against normal blind 0.8 bodies 2
chamfer "SW1 spring 1 45 degree lead-in" distance 0.35 angle 45 1 edges at (10.2843, 28.9414, 15.6717) tangent chain off on bodies 2
sketch "SW1 spring 2 release 1 profile" plane through (0, -2.056, 23.4999) normal (0, -0.087156, 0.996195) x (1, 0, 0)
  line L0 (21.2157, 28.5972) -> (24.8, 28.5972)
  line L1 (24.8, 28.5972) -> (24.8, 29.1972)
  line L2 (24.8, 29.1972) -> (21.2157, 29.1972)
  line L3 (21.2157, 29.1972) -> (21.2157, 28.5972)
  dimension "d939" = 21.2157
  dimension "d940" = 28.5972
  dimension "d941" = 3.5843
  dimension "d942" = 0.6
  constraint horizontal L0
  constraint vertical L1
  constraint horizontal L2
  constraint vertical L3
  measures "d939" horizontal distance of origin L0.start
  measures "d940" vertical distance of origin L0.start
  measures "d941" distance of L0.start L0.end
  measures "d942" distance of L0.end L1.end
extrude "SW1 spring 2 release 1" cut sketch "SW1 spring 2 release 1 profile" against normal blind 10.7 bodies 2
sketch "SW1 spring 2 release 2 profile" plane through (0, -2.056, 23.4999) normal (0, -0.087156, 0.996195) x (1, 0, 0)
  line L0 (21.2157, 31.1972) -> (24.8, 31.1972)
  line L1 (24.8, 31.1972) -> (24.8, 31.7972)
  line L2 (24.8, 31.7972) -> (21.2157, 31.7972)
  line L3 (21.2157, 31.7972) -> (21.2157, 31.1972)
  dimension "d945" = 21.2157
  dimension "d946" = 31.1972
  dimension "d947" = 3.5843
  dimension "d948" = 0.6
  constraint horizontal L0
  constraint vertical L1
  constraint horizontal L2
  constraint vertical L3
  measures "d945" horizontal distance of origin L0.start
  measures "d946" vertical distance of origin L0.start
  measures "d947" distance of L0.start L0.end
  measures "d948" distance of L0.end L1.end
extrude "SW1 spring 2 release 2" cut sketch "SW1 spring 2 release 2 profile" against normal blind 10.7 bodies 2
sketch "SW1 spring 2 inner clearance profile" plane through (0, -1.6638, 19.017) normal (0, -0.087156, 0.996195) x (1, 0, 0)
  line L0 (21.2157, 29.1972) -> (23.9, 29.1972)
  line L1 (23.9, 29.1972) -> (23.9, 31.1972)
  line L2 (23.9, 31.1972) -> (21.2157, 31.1972)
  line L3 (21.2157, 31.1972) -> (21.2157, 29.1972)
  dimension "d951" = 21.2157
  dimension "d952" = 29.1972
  dimension "d953" = 2.6843
  dimension "d954" = 2
  constraint horizontal L0
  constraint vertical L1
  constraint horizontal L2
  constraint vertical L3
  measures "d951" horizontal distance of origin L0.start
  measures "d952" vertical distance of origin L0.start
  measures "d953" distance of L0.start L0.end
  measures "d954" distance of L0.end L1.end
extrude "SW1 spring 2 inner clearance" cut sketch "SW1 spring 2 inner clearance profile" against normal blind 6.2 bodies 2
sketch "SW1 spring 2 hook profile" plane through (0, -1.2106, 13.8368) normal (0, -0.087156, 0.996195) x (1, 0, 0)
  line L0 (20.7157, 29.1972) -> (24.7, 29.1972)
  line L1 (24.7, 29.1972) -> (24.7, 31.1972)
  line L2 (24.7, 31.1972) -> (20.7157, 31.1972)
  line L3 (20.7157, 31.1972) -> (20.7157, 29.1972)
  dimension "d957" = 20.7157
  dimension "d958" = 29.1972
  dimension "d959" = 3.9843
  dimension "d960" = 2
  constraint horizontal L0
  constraint vertical L1
  constraint horizontal L2
  constraint vertical L3
  measures "d957" horizontal distance of origin L0.start
  measures "d958" vertical distance of origin L0.start
  measures "d959" distance of L0.start L0.end
  measures "d960" distance of L0.end L1.end
extrude "SW1 spring 2 retaining hook" add sketch "SW1 spring 2 hook profile" against normal blind 0.8 bodies 2
chamfer "SW1 spring 2 45 degree lead-in" distance 0.35 angle 45 1 edges at (20.7157, 28.9414, 15.6717) tangent chain off on bodies 2
sketch "SW1 support 1 reinforced stem profile" plane through (0, 0, 2) normal (0, 0, 1) x (1, 0, 0)
  line L0 (11.8, 21.5078) -> (14.2, 21.5078)
  line L1 (14.2, 21.5078) -> (14.2, 26.5078)
  line L2 (14.2, 26.5078) -> (11.8, 26.5078)
  line L3 (11.8, 26.5078) -> (11.8, 21.5078)
  dimension "d964" = 11.8
  dimension "d965" = 21.5078
  dimension "d966" = 2.4
  dimension "d967" = 5
  constraint horizontal L0
  constraint vertical L1
  constraint horizontal L2
  constraint vertical L3
  measures "d964" horizontal distance of origin L0.start
  measures "d965" vertical distance of origin L0.start
  measures "d966" distance of L0.start L0.end
  measures "d967" distance of L0.end L1.end
extrude "SW1 support 1 reinforced stem" add sketch "SW1 support 1 reinforced stem profile" along normal blind 11.8423 bodies 3
sketch "SW1 support 1 profile" plane through (0, 0, 2) normal (0, 0, 1) x (1, 0, 0)
  line L0 (12.5, 22.5078) -> (13.5, 22.5078)
  line L1 (13.5, 22.5078) -> (13.5, 25.5078)
  line L2 (13.5, 25.5078) -> (12.5, 25.5078)
  line L3 (12.5, 25.5078) -> (12.5, 22.5078)
  dimension "d970" = 12.5
  dimension "d971" = 22.5078
  dimension "d972" = 1
  dimension "d973" = 3
  constraint horizontal L0
  constraint vertical L1
  constraint horizontal L2
  constraint vertical L3
  measures "d970" horizontal distance of origin L0.start
  measures "d971" vertical distance of origin L0.start
  measures "d972" distance of L0.start L0.end
  measures "d973" distance of L0.end L1.end
extrude "SW1 support 1" add sketch "SW1 support 1 profile" along normal blind 14.3423 bodies 3
sketch "SW1 support 1 cap profile" plane through (0, -1.1931, 13.6376) normal (0, -0.087156, 0.996195) x (1, 0, 0)
  line L0 (12.4, 23.2972) -> (13.6, 23.2972)
  line L1 (13.6, 23.2972) -> (13.6, 27.2972)
  line L2 (13.6, 27.2972) -> (12.4, 27.2972)
  line L3 (12.4, 27.2972) -> (12.4, 23.2972)
  dimension "d976" = 12.4
  dimension "d977" = 23.2972
  dimension "d978" = 1.2
  dimension "d979" = 4
  constraint horizontal L0
  constraint vertical L1
  constraint horizontal L2
  constraint vertical L3
  measures "d976" horizontal distance of origin L0.start
  measures "d977" vertical distance of origin L0.start
  measures "d978" distance of L0.start L0.end
  measures "d979" distance of L0.end L1.end
extrude "SW1 support 1 inclined cap" cut sketch "SW1 support 1 cap profile" along normal blind 39.0612 bodies 3
sketch "SW1 support 2 reinforced stem profile" plane through (0, 0, 2) normal (0, 0, 1) x (1, 0, 0)
  line L0 (16.8, 21.5078) -> (19.2, 21.5078)
  line L1 (19.2, 21.5078) -> (19.2, 26.5078)
  line L2 (19.2, 26.5078) -> (16.8, 26.5078)
  line L3 (16.8, 26.5078) -> (16.8, 21.5078)
  dimension "d982" = 16.8
  dimension "d983" = 21.5078
  dimension "d984" = 2.4
  dimension "d985" = 5
  constraint horizontal L0
  constraint vertical L1
  constraint horizontal L2
  constraint vertical L3
  measures "d982" horizontal distance of origin L0.start
  measures "d983" vertical distance of origin L0.start
  measures "d984" distance of L0.start L0.end
  measures "d985" distance of L0.end L1.end
extrude "SW1 support 2 reinforced stem" add sketch "SW1 support 2 reinforced stem profile" along normal blind 11.8423 bodies 3
sketch "SW1 support 2 profile" plane through (0, 0, 2) normal (0, 0, 1) x (1, 0, 0)
  line L0 (17.5, 22.5078) -> (18.5, 22.5078)
  line L1 (18.5, 22.5078) -> (18.5, 25.5078)
  line L2 (18.5, 25.5078) -> (17.5, 25.5078)
  line L3 (17.5, 25.5078) -> (17.5, 22.5078)
  dimension "d988" = 17.5
  dimension "d989" = 22.5078
  dimension "d990" = 1
  dimension "d991" = 3
  constraint horizontal L0
  constraint vertical L1
  constraint horizontal L2
  constraint vertical L3
  measures "d988" horizontal distance of origin L0.start
  measures "d989" vertical distance of origin L0.start
  measures "d990" distance of L0.start L0.end
  measures "d991" distance of L0.end L1.end
extrude "SW1 support 2" add sketch "SW1 support 2 profile" along normal blind 14.3423 bodies 3
sketch "SW1 support 2 cap profile" plane through (0, -1.1931, 13.6376) normal (0, -0.087156, 0.996195) x (1, 0, 0)
  line L0 (17.4, 23.2972) -> (18.6, 23.2972)
  line L1 (18.6, 23.2972) -> (18.6, 27.2972)
  line L2 (18.6, 27.2972) -> (17.4, 27.2972)
  line L3 (17.4, 27.2972) -> (17.4, 23.2972)
  dimension "d994" = 17.4
  dimension "d995" = 23.2972
  dimension "d996" = 1.2
  dimension "d997" = 4
  constraint horizontal L0
  constraint vertical L1
  constraint horizontal L2
  constraint vertical L3
  measures "d994" horizontal distance of origin L0.start
  measures "d995" vertical distance of origin L0.start
  measures "d996" distance of L0.start L0.end
  measures "d997" distance of L0.end L1.end
extrude "SW1 support 2 inclined cap" cut sketch "SW1 support 2 cap profile" along normal blind 39.0612 bodies 3